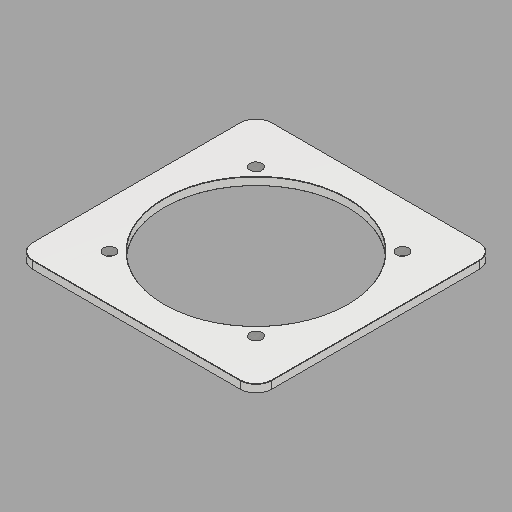
# Autodesk Inventor part: BT025_thutrn22_26
Saved by Autodesk Inventor 2025.3 (Build 293356000, 356)
## iProperties
Company: HTBLA Kaindorf
RuleStatus: InUse
Created: 2026-08-19
Part Number: BT025_thutrn22_26
Project: Biegeroboter
Material: ABS-Kunststoff
Description: gehaeuse_deckel_getriebe
Document SubType Name: Modeling
Designer: thutrn22
Density: 1.06 g/cm^3
Appearance: Glatt - Weiß
Mass: 62.7309 g
Surface Area: 286.67 cm^2
Volume: 59.1801 cm^3
AfterDocNew0: iProperties-Editor_aufrufen
Author: trist
Keywords: 2026
Autodesk Inventor part; units mm, degrees
ref_plane "YZ Plane" through (0, 0, 0) normal (1, 0, 0) x (0, 1, 0)
ref_plane "XZ Plane" through (0, 0, 0) normal (0, 1, 0) x (-1, 0, 0)
ref_plane "XY Plane" through (0, 0, 0) normal (0, 0, 1) x (1, 0, 0)
sketch "Skizze3" plane through (0, 0, 0) normal (0, 0, 1) x (1, 0, 0)
  line L0 (0, -105) -> (0, 105) projected
  line L1 (-105, 0) -> (105, 0) projected
  line L2 (-75, 75) -> (75, 75)
  line L3 (75, 75) -> (75, -75)
  line L4 (75, -75) -> (-75, -75)
  line L5 (-75, -75) -> (-75, 75)
  circle A0 centre (0, 0) radius 57.5
  circle A1 centre (-45.962, 45.962) radius 4.5
  circle A2 centre (45.962, 45.962) radius 4.5
  circle A3 centre (-45.962, -45.962) radius 4.5
  circle A4 centre (45.962, -45.962) radius 4.5
  dimension "d4" = 150
  dimension "d5" = 150
  dimension "d6" = 115
  dimension "d7" = 9
  dimension "d8" = 45.962
  dimension "d9" = 45.962
  constraints: 8 end point, 5 centre point, 5 coincident, 3 symmetric about line, 2 parallel, 1 horizontal, 1 perpendicular, 5 other
  measures "d4" distance of L3.end L4.end
  measures "d5" distance of L2.end L3.end
  measures "d6" diameter of A0
  measures "d7" diameter of A1
  measures "d8" distance from line of L1 A1.centre
  measures "d9" distance from line of L0 A1.centre
extrude "Extrusion3" add sketch "Skizze3" along normal blind 5 contours L4 L5 L1 A0 L0 | L0 A0 L1 L3 L4 | L1 L5 L2 L0 A0 | A0 L0 L2 L3 L1 | A1 | A2 | A3 | A4
fillet "Rundung1" radius 10 4 edges at (75, 75, 2.5) (75, -75, 2.5) (-75, -75, 2.5) (-75, 75, 2.5)
chamfer "Fasen1" distance 0.2 angle 45 16 edges at (-75, 0, 5) (-72.0711, -72.0711, 5) (0, -75, 5) (72.0711, -72.0711, 5) (75, 0, 5) (72.0711, 72.0711, 5) (0, 75, 5) (-72.0711, 72.0711, 5) (-75, 0, 0) (-72.0711, -72.0711, 0) (0, -75, 0) (72.0711, -72.0711, 0) (75, 0, 0) (72.0711, 72.0711, 0) (0, 75, 0) (-72.0711, 72.0711, 0)
chamfer "Fasen2" distance 0.2 angle 45 2 edges at (-57.5, 0, 5) (-57.5, 0, 0)
hole "Bohrung1" at (-45.962, -45.962, 0) at (45.962, -45.962, 0) at (45.962, 45.962, 0) at (-45.962, 45.962, 0) direction (0, 0, 1) diameter 7.6468 end through all thread size "M9x1.25" class "6H" standard "ISO Metric profile"
